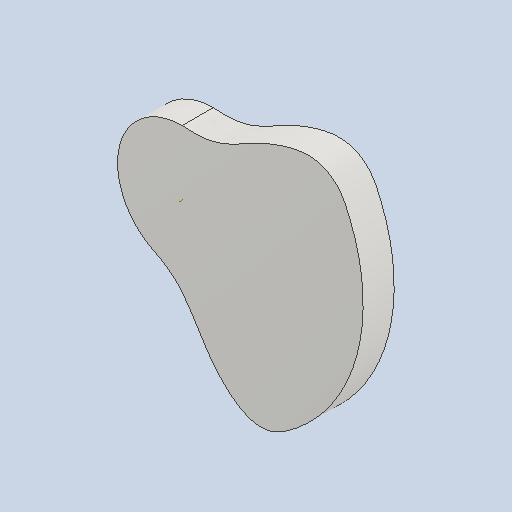
# Autodesk Inventor part: Leva de disco
Saved by Autodesk Inventor 2024 (Build 280153000, 153)
## iProperties
Created: 2024-05-23
Part Number: Leva de disco
Material: Stainless Steel, Austenitic
Document SubType Name: Modeling
Designer: PC
Manufacturer: Standard
Standards Organization: Custom
Density: 1 g/cm^3
Appearance: Steel
CustomPartVersion: 1
Author: PC
Autodesk Inventor part; units mm, degrees
ref_plane "YZ Plane" through (0, 0, 0) normal (1, 0, 0) x (0, 1, 0)
ref_plane "XZ Plane" through (0, 0, 0) normal (0, 1, 0) x (-1, 0, 0)
ref_plane "XY Plane" through (0, 0, 0) normal (0, 0, 1) x (1, 0, 0)
sketch "Boceto principal" plane through (0, 0, 0) normal (0, 0, 1) x (1, 0, 0)
  spline S0 degree 5 poles (0.0012, 25) (0.6488, 24.9982) (1.7723, 24.962) (3.5205, 24.843) (5.5094, 24.7885) (9.3701, 24.9659) (13.3537, 25.9053) (17.2321, 27.2737) (23.9511, 30.6874) (32.2073, 35.7202) (42.9356, 39.1138) (52.1881, 40.8564) (61.2741, 35.3847) (63.787, 28.7618) (66.8049, 21.8587) (68.6303, 14.5818) (69.8213, 7.2656) (70.2043, 0.0112) (69.7634, -7.6643) (68.6993, -14.3112) (66.77, -21.7358) (64.1016, -28.5445) (60.838, -35.0643) (56.5892, -41.4976) (52.4011, -46.6832) (46.8202, -52.3508) (41.2436, -56.7084) (34.1429, -61.7113) (25.3654, -61.2559) (17.1093, -55.1728) (10.0154, -47.1078) (5.1593, -37.6838) (0.2154, -31.1286) (-1.6381, -28.6154) (-5.9308, -25.254) (-7.4883, -24.3326) (-10.177, -22.8402) (-12.5372, -21.7312) (-14.7337, -20.2792) (-16.8465, -18.5615) (-18.5459, -16.859) (-20.2918, -14.7303) (-21.6952, -12.5581) (-22.9123, -10.1703) (-23.8434, -7.7586) (-24.5421, -5.0941) (-24.914, -2.7219) (-25.078, 0.0148) (-24.9237, 2.6196) (-24.533, 5.1995) (-23.8037, 7.8424) (-22.9467, 10.0853) (-21.7093, 12.5465) (-20.2971, 14.7116) (-18.6101, 16.7949) (-16.7859, 18.6262) (-14.6358, 20.3485) (-12.6202, 21.6526) (-10.1849, 22.9176) (-7.8387, 23.797) (-5.3238, 24.5073) (-3.1652, 24.8339) (-1.6657, 24.9737) (-0.6294, 25.0017) (0.0012, 25) knots 0 0 0 0 0 0 0.015349 0.026206 0.040129 0.055435 0.073328 0.093846 0.116221 0.140039 0.164001 0.187018 0.208781 0.229858 0.250629 0.271548 0.29243 0.313312 0.334195 0.355077 0.375959 0.396841 0.417723 0.438581 0.459523 0.480559 0.502415 0.525524 0.549799 0.573707 0.596386 0.617162 0.634753 0.649464 0.662785 0.67555 0.68784 0.700291 0.712788 0.725267 0.737747 0.750226 0.762785 0.775265 0.787744 0.800224 0.812703 0.825182 0.837662 0.850141 0.862621 0.8751 0.887579 0.900139 0.912618 0.925097 0.937577 0.950056 0.962536 0.975052 0.985057 1 1 1 1 1 1
  point P0 (5.232, 24.8399)
  point P1 (8.5871, 25.0343)
  point P2 (12.377, 25.7543)
  point P3 (16.119, 27.0025)
  point P4 (21.9142, 29.7576)
  point P5 (31.4136, 34.7036)
  point P6 (43.2185, 38.7736)
  point P7 (53.2492, 38.8316)
  point P8 (60.4647, 34.2833)
  point P9 (63.9859, 28.3525)
  point P10 (66.5348, 21.7514)
  point P11 (68.4616, 14.595)
  point P12 (69.6209, 7.2751)
  point P13 (69.9999, -0.1264)
  point P14 (69.5942, -7.5264)
  point P15 (68.5052, -14.3889)
  point P16 (66.5999, -21.551)
  point P17 (63.9482, -28.4716)
  point P18 (60.5796, -35.0729)
  point P19 (56.532, -41.2812)
  point P20 (52.1608, -46.6824)
  point P21 (46.933, -51.9355)
  point P22 (41.2372, -56.547)
  point P23 (34.4474, -60.1923)
  point P24 (26.6993, -60.2538)
  point P25 (18.0416, -55.1882)
  point P26 (9.8531, -45.761)
  point P27 (3.4128, -35.6477)
  point P28 (-0.3691, -30.4311)
  point P29 (-3.1128, -27.589)
  point P30 (-6.0562, -25.2795)
  point P31 (-7.8889, -24.128)
  point P32 (-10.1293, -22.9106)
  point P33 (-12.5, -21.6506)
  point P34 (-14.719, -20.2077)
  point P35 (-16.7729, -18.5383)
  point P36 (-18.5282, -16.7841)
  point P37 (-20.1989, -14.7311)
  point P38 (-21.6431, -12.513)
  point P39 (-22.8448, -10.1547)
  point P40 (-23.7903, -7.6825)
  point P41 (-24.4692, -5.1242)
  point P42 (-24.8567, -2.6731)
  point P43 (-25, -0.0301)
  point P44 (-24.863, 2.6132)
  point P45 (-24.4474, 5.2272)
  point P46 (-23.7577, 7.7826)
  point P47 (-22.8691, 10.0996)
  point P48 (-21.6732, 12.4609)
  point P49 (-20.2343, 14.6825)
  point P50 (-18.5685, 16.7394)
  point P51 (-16.6947, 18.6088)
  point P52 (-14.6337, 20.2696)
  point P53 (-12.5521, 21.6205)
  point P54 (-10.1959, 22.8264)
  point P55 (-7.7254, 23.7764)
  point P56 (-5.1684, 24.4599)
  point P57 (-2.5533, 24.8693)
  constraints: 60 other
extrude "Leva" add sketch "Boceto principal" along normal blind 12
body "Solid1"
